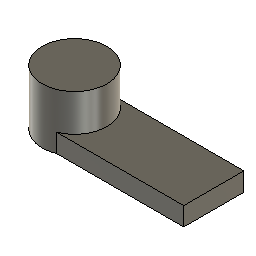
LAMP BUTTON (Autodesk Fusion 360 design; units mm, degrees)
part number: 2026-05-20-23-07-59-793
Autodesk Fusion 360 part; units mm, degrees
sketch "Sketch1" plane through (0, 0, 0) normal (0, 0, 1) x (1, 0, 0)
  circle A0 centre (0, 0) radius 3.5
  line L0 (1.299, 3.25) -> (15.041, 3.25)
  line L1 (1.299, -3.25) -> (15.041, -3.25)
  line L2 (15.041, 3.25) -> (15.041, -3.25)
  dimension "d1" = 7
  dimension "d2" = 13.742
  dimension "d3" = 13.742
  dimension "d4" = 6.5
  dimension "d5" = 3.25
  constraint coincident A0.centre origin
  constraint coincident A0 L0.start
  constraint horizontal L0
  constraint coincident A0 L1.start
  constraint horizontal L1
  measures "d1" diameter of A0
  measures "d2" distance of L1.start L1.end
  measures "d3" distance of L0.start L0.end
  measures "d4" distance of L0 L1
  measures "d5" distance of A0.centre L0
extrude "Extrude1" add sketch "Sketch1" against normal blind 6 contours A0
extrude "Extrude2" add sketch "Sketch1" along normal blind 2 from surface at -6 contours A0 L0 L1 L2
